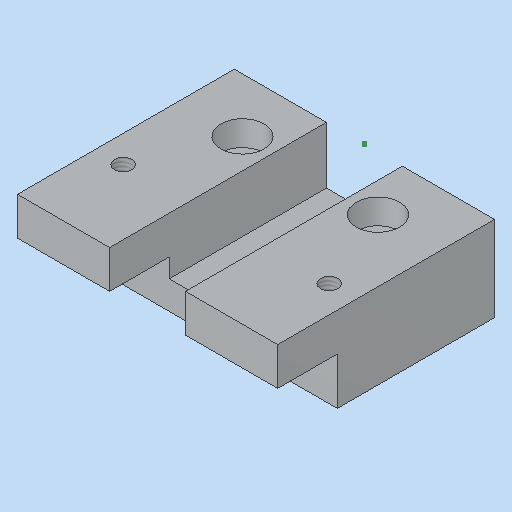
# Autodesk Inventor part: MM0948AN160_G01_111
Saved by Autodesk Inventor 2023.3 (Build 273359000, 359)
## iProperties
RuleStatus: InUse
Created: 2023-03-23
Part Number: MM0948AN160_G01_111
Material: 3.3547 AlMg4,5Mn0,7 - AW 5083
Description: =<RBPARTNOTITLE2>
Document SubType Name: Modeling
Designer: ric7an
Mass: 51.7071 g
Surface Area: 73.3382 cm^2
Volume: 19.1508 cm^3
Density: 2.7 g/cm^3
Appearance: Aluminium AnP
AnP_Kategorie: 1
AnP_Material: =<Material>
MaxAbmaße: 38 x 20,7 x 48 (FM)
AnP_TemplVers: 20200821
RBDOCUMENTTYPE: DRF
RBDOCUMENTVERSION: 00
RBDRAWINGMAINSCALE: 1:1
RBDRAWINGMISSINGSPEC: --
RBDRAWINGVOLUME: --
RBDSV1: 0850
RBGBEDGESIN1: +0,5
RBGBEDGESIN2: +0,2
RBGBEDGESOUT1: -0,3
RBGBEDGESOUT2: -0,1
RBMATERIAL: =<Material>
RBMATMEETS: --
RBMATNO: =<Part Number>
RBPARTMADEOF: 38 x 20,7 x 48 (FM)
RBPARTNO: SIEHE MNR
RBPARTNOTITLE1: manufactured part
RBPARTNOTITLE2: Anfertigungsteil
RBPARTSAFETYINDICATOR: --
RBSURFACE: anodised colourless
RBSURFACE2: eloxiert farblos
RBZEDGESNORM: ISO13715:2002-06
RBZGENDIMCLASS: m
RBZGENDIMNORM: ISO 2768-1:1989-11
RBZGENGEOCLASS: H
RBZGENGEONORM: ISO 2768-2:1989-11
RBZSURFACENORM: ISO13D2:2002-02
RBZTOLERANCENORM: ISO 14405-1:2010-12
AnP_Kommentar_aktuell: =<Comments>
AnP_Material_aktuell: =<Material>
Author: FH/Wi
Keywords: =<RBPARTMADEOF>
Comments: =<RBSURFACE2>
Revision Number: 01
Autodesk Inventor part; units mm, degrees
ref_plane "YZ Plane" through (0, 0, 0) normal (1, 0, 0) x (0, 1, 0)
ref_plane "XZ Plane" through (0, 0, 0) normal (0, 1, 0) x (-1, 0, 0)
ref_plane "XY Plane" through (0, 0, 0) normal (0, 0, 1) x (1, 0, 0)
sketch "Skizze1" plane through (0, 0, 0) normal (0, 0, 1) x (1, 0, 0)
  line L0 (-24, 15.7) -> (24, 15.7)
  line L1 (24, 15.7) -> (24, 0)
  line L2 (24, 0) -> (-24, 0)
  line L3 (-24, 0) -> (-24, 15.7)
  line L4 (-33.6, 0) -> (33.6, 0) projected
  line L5 (0, 24.84) -> (0, -4.14) projected
  point P0 (0, 0)
  dimension "d0" = 48
  dimension "d1" = 15.7
  constraints: 8 end point, 2 parallel, 1 collinear, 1 horizontal, 1 perpendicular, 1 other
  measures "d0" distance of L0.start L0.end
  measures "d1" distance of L0.end L1.end
extrude "Extrusion1" add sketch "Skizze1" along normal blind 40
sketch "Skizze2" plane through (-1.5, 15.7, 20) normal (0, 1, 0) x (1, 0, 0)
  line L0 (1.5, 28) -> (1.5, -28) projected
  line L1 (-22.5, -20) -> (25.5, -20) projected
  line L2 (25.5, 20) -> (-22.5, 20) projected
  point P0 (1.5, 20)
  point P1 (-17.5, -5.5)
  point P2 (20.5, -5.5)
  dimension "d5" = 38
  dimension "d40" = 14.5
  constraints: 1 symmetric about line, 1 other
  measures "d5" distance of point (20.5, -5.5) point (-17.5, -5.5)
hole "Bohrung1" at (-19, 15.7, 25.5) at (19, 15.7, 25.5) direction (0, -1, 0) diameter 3.242 depth 11.8 tip angle 118 thread size "M4x0.7" designation "M4" class "6H" standard "ISO Metric profile"
sketch "Skizze3" plane through (-24, 15.7, 0) normal (0, 1, 0) x (1, 0, 0)
  line L0 (24, 8) -> (24, -48) projected
  line L1 (57.6, 0) -> (-9.6, 0) projected
  line L2 (48, -40) -> (0, -40) projected
  point P0 (24, 0)
  point P1 (11.5, -10)
  point P2 (36.5, -10)
  dimension "d14" = 25
  dimension "d41" = 30
  constraints: 1 horizontal alignment, 1 symmetric about line
  measures "d14" distance of point (36.5, -10) point (11.5, -10)
  measures "d41" distance from line of L2 point (11.5, -10)
hole "Bohrung2" at (-12.5, 15.7, 10) at (12.5, 15.7, 10) direction (0, -1, 0) diameter 4.5 end through all counterbore diameter 8 counterbore depth 4.6 clearance for "Inbusschraube ISO 4762  versenkt" size "M4" standard "ISO"
sketch "Skizze4" plane through (24, 0, 0) normal (1, 0, 0) x (0, 0, -1)
  line L0 (-40, 8.7) -> (-29, 8.7)
  line L1 (-29, 8.7) -> (-29, 0)
  line L2 (-29, 0) -> (-40, 0)
  line L3 (-40, 0) -> (-40, 8.7)
  line L4 (0, 15.7) -> (-40, 15.7) projected
  line L5 (0, 0) -> (0, 15.7) projected
  dimension "d23" = 7
  dimension "d42" = 11
  constraints: 8 end point, 2 parallel, 1 coincident, 1 horizontal, 1 perpendicular
  measures "d23" distance between parallel lines of L0 L4
  measures "d42" distance of L0.start L0.end
extrude "Extrusion2" cut sketch "Skizze4" against normal through all
sketch "Skizze5" plane through (-24, 15.7, 0) normal (0, 1, 0) x (1, 0, 0)
  point P0 (24, 0)
sketch "Skizze6" plane through (-24, 15.7, 0) normal (0, 1, 0) x (1, 0, 0)
  circle A0 centre (11.5, -10) radius 4 projected
  circle A1 centre (36.5, -10) radius 4 projected
  circle A2 centre (5, -25.5) radius 1.621 projected
  circle A3 centre (43, -25.5) radius 1.621 projected
  line L0 (48, 0) -> (0, 0) projected
  line L1 (0, 0) -> (0, -40) projected
  line L2 (48, -40) -> (0, -40) projected
  line L3 (48, 0) -> (48, -40) projected
  line L4 (17, 0) -> (31, 0)
  line L5 (31, 0) -> (31, -40)
  line L6 (31, -40) -> (17, -40)
  line L7 (17, -40) -> (17, 0)
  line L8 (24, 8) -> (24, -48) projected
  point P0 (24, 0)
  dimension "d28" = 14
  constraints: 8 end point, 2 parallel, 2 point on line, 1 horizontal, 1 perpendicular, 1 other
  measures "d28" distance between parallel lines of L5 L7
extrude "Extrusion3" cut sketch "Skizze6" against normal blind 10.5 contours L5 L2 L8 L0 | L8 L2 L7 L0
sketch "Skizze7" plane through (-24, 5.2, 0) normal (0, 1, 0) x (1, 0, 0)
  line L0 (24, 8) -> (24, -48) projected
  line L1 (31, -29) -> (17, -29) projected
  line L2 (17, 0) -> (31, 0) projected
  point P0 (24, 0)
  point P1 (24, -4)
  dimension "d43" = 4
  constraints: 1 point on line
  measures "d43" distance from line of L2 point (24, -4)
hole "Bohrung3" at (0, 5.2, 4) direction (0, -1, 0) diameter 3.242 end through all thread size "M4x0.7" designation "M4" class "6H" standard "ISO Metric profile"
